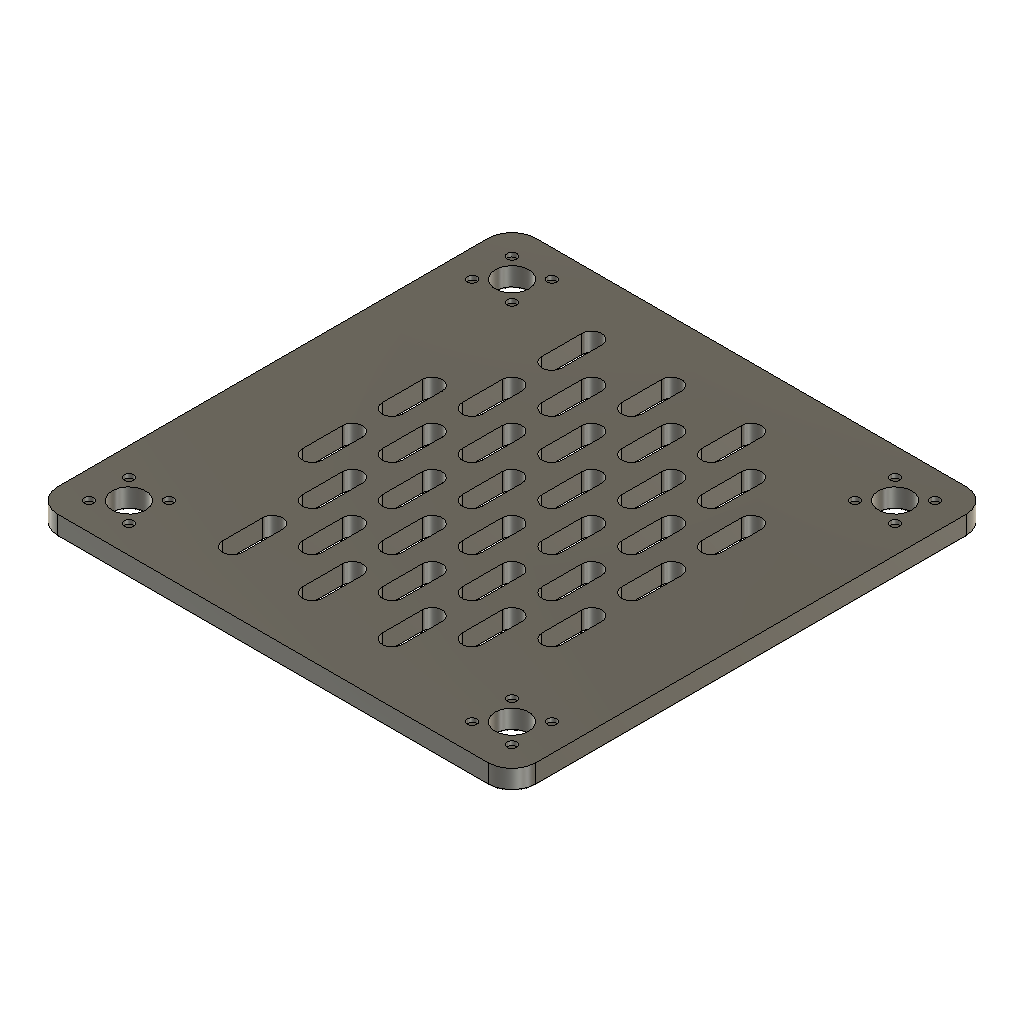
panel-standalone-v03 (Autodesk Fusion 360 design; units mm, degrees)
part number: 2026-10-27-17-32-38-234
part number: 2026-10-27-17-32-38-962
Autodesk Fusion 360 part; units mm, degrees
sketch "01 Panel blank sketch" plane through (0, 0, 0) normal (0, 0, 1) x (1, 0, 0) in component "Panel standalone"
  line L0 (0.1, 0.1) -> (119.9, 0.1)
  line L1 (119.9, 0.1) -> (119.9, 119.9)
  line L2 (119.9, 119.9) -> (0.1, 119.9)
  line L3 (0.1, 119.9) -> (0.1, 0.1)
  dimension "d57" = 0.1
  dimension "d58" = 0.1
  dimension "d59" = 119.8
  dimension "d60" = 119.8
  constraint horizontal L0
  constraint vertical L1
  constraint horizontal L2
  constraint vertical L3
  measures "d57" horizontal distance of origin L0.start
  measures "d58" vertical distance of origin L0.start
  measures "d59" horizontal distance of L0.start L0.end
  measures "d60" vertical distance of L0.end L1.end
extrude "01 Panel blank" add sketch "01 Panel blank sketch" along normal blind 5 in component "Panel standalone"
fillet "02 Rounded exterior corners" radius 6 4 edges at (0.1, 119.9, 2.5) (119.9, 119.9, 2.5) (119.9, 0.1, 2.5) (0.1, 0.1, 2.5) in component "Panel standalone"
sketch "03 A main constrained seed" plane through (0, 0, 0) normal (0, 0, 1) x (1, 0, 0) in component "Panel standalone"
  line L0 (47.5, 25) -> (47.5, 35)
  arc A0 (47.5, 35) -> (42.5, 35) centre (45, 35) ccw
  line L1 (42.5, 35) -> (42.5, 25)
  arc A1 (42.5, 25) -> (47.5, 25) centre (45, 25) ccw
  line L2 (45, 25) -> (45, 35) construction
  line L3 (45, 25) -> (55, 25) construction
  dimension "d65" = 5
  dimension "d66" = 10
  dimension "d67" = 90
  dimension "d68" = 10
  dimension "d69" = 45
  dimension "d70" = 25
  constraint tangent L0 A0
  constraint tangent A0 L1
  constraint tangent L1 A1
  constraint tangent L0 A1
  constraint parallel L0 L1
  constraint horizontal L3
  measures "d65" diameter of A0
  measures "d66" distance of A1.centre A0.centre
  measures "d67" angle of L2 L3
  measures "d68" horizontal distance of A1.centre L3.end
  measures "d69" horizontal distance of origin A1.centre
  measures "d70" vertical distance of origin A1.centre
extrude "03 A main through cut" cut sketch "03 A main constrained seed" along normal blind 5 in component "Panel standalone"
pattern_linear "03 A main lattice" count 3 spacing 20 along (1, 0, 0) count 4 spacing 20 along (0, 1, 0) of "03 A main through cut" in component "Panel standalone"
sketch "04 A end strip constrained seed" plane through (0, 0, 0) normal (0, 0, 1) x (1, 0, 0) in component "Panel standalone"
  line L0 (27.5, 45) -> (27.5, 55)
  arc A0 (27.5, 55) -> (22.5, 55) centre (25, 55) ccw
  line L1 (22.5, 55) -> (22.5, 45)
  arc A1 (22.5, 45) -> (27.5, 45) centre (25, 45) ccw
  line L2 (25, 45) -> (25, 55) construction
  line L3 (25, 45) -> (35, 45) construction
  dimension "d77" = 5
  dimension "d78" = 10
  dimension "d79" = 90
  dimension "d80" = 10
  dimension "d81" = 25
  dimension "d82" = 45
  constraint tangent L0 A0
  constraint tangent A0 L1
  constraint tangent L1 A1
  constraint tangent L0 A1
  constraint parallel L0 L1
  constraint horizontal L3
  measures "d77" diameter of A0
  measures "d78" distance of A1.centre A0.centre
  measures "d79" angle of L2 L3
  measures "d80" horizontal distance of A1.centre L3.end
  measures "d81" horizontal distance of origin A1.centre
  measures "d82" vertical distance of origin A1.centre
extrude "04 A end strip through cut" cut sketch "04 A end strip constrained seed" along normal blind 5 in component "Panel standalone"
pattern_linear "04 A end strip lattice" count 1 spacing 20 along (1, 0, 0) count 2 spacing 20 along (0, 1, 0) of "04 A end strip through cut" in component "Panel standalone"
sketch "05 B main constrained seed" plane through (0, 0, 0) normal (0, 0, 1) x (1, 0, 0) in component "Panel standalone"
  line L0 (37.5, 15) -> (37.5, 25)
  arc A0 (37.5, 25) -> (32.5, 25) centre (35, 25) ccw
  line L1 (32.5, 25) -> (32.5, 15)
  arc A1 (32.5, 15) -> (37.5, 15) centre (35, 15) ccw
  line L2 (35, 15) -> (35, 25) construction
  line L3 (35, 15) -> (45, 15) construction
  dimension "d89" = 5
  dimension "d90" = 10
  dimension "d91" = 90
  dimension "d92" = 10
  dimension "d93" = 35
  dimension "d94" = 15
  constraint tangent L0 A0
  constraint tangent A0 L1
  constraint tangent L1 A1
  constraint tangent L0 A1
  constraint parallel L0 L1
  constraint horizontal L3
  measures "d89" diameter of A0
  measures "d90" distance of A1.centre A0.centre
  measures "d91" angle of L2 L3
  measures "d92" horizontal distance of A1.centre L3.end
  measures "d93" horizontal distance of origin A1.centre
  measures "d94" vertical distance of origin A1.centre
extrude "05 B main through cut" cut sketch "05 B main constrained seed" along normal blind 5 in component "Panel standalone"
pattern_linear "05 B main lattice" count 3 spacing 20 along (1, 0, 0) count 5 spacing 20 along (0, 1, 0) of "05 B main through cut" in component "Panel standalone"
sketch "06 B end strip constrained seed" plane through (0, 0, 0) normal (0, 0, 1) x (1, 0, 0) in component "Panel standalone"
  line L0 (97.5, 35) -> (97.5, 45)
  arc A0 (97.5, 45) -> (92.5, 45) centre (95, 45) ccw
  line L1 (92.5, 45) -> (92.5, 35)
  arc A1 (92.5, 35) -> (97.5, 35) centre (95, 35) ccw
  line L2 (95, 35) -> (95, 45) construction
  line L3 (95, 35) -> (105, 35) construction
  dimension "d101" = 5
  dimension "d102" = 10
  dimension "d103" = 90
  dimension "d104" = 10
  dimension "d105" = 95
  dimension "d106" = 35
  constraint tangent L0 A0
  constraint tangent A0 L1
  constraint tangent L1 A1
  constraint tangent L0 A1
  constraint parallel L0 L1
  constraint horizontal L3
  measures "d101" diameter of A0
  measures "d102" distance of A1.centre A0.centre
  measures "d103" angle of L2 L3
  measures "d104" horizontal distance of A1.centre L3.end
  measures "d105" horizontal distance of origin A1.centre
  measures "d106" vertical distance of origin A1.centre
extrude "06 B end strip through cut" cut sketch "06 B end strip constrained seed" along normal blind 5 in component "Panel standalone"
pattern_linear "06 B end strip lattice" count 1 spacing 20 along (1, 0, 0) count 3 spacing 20 along (0, 1, 0) of "06 B end strip through cut" in component "Panel standalone"
sketch "07 Shared node clearance sketch" plane through (0, 0, 0) normal (0, 0, 1) x (1, 0, 0) in component "Panel standalone"
  circle A0 centre (12, 12) radius 4.2
  dimension "d113" = 12
  dimension "d114" = 12
  dimension "d115" = 8.4
  measures "d113" horizontal distance of origin A0.centre
  measures "d114" vertical distance of origin A0.centre
  measures "d115" diameter of A0
extrude "07 Shared node clearance" cut sketch "07 Shared node clearance sketch" along normal blind 5 in component "Panel standalone"
sketch "07 Shared node clearance sketch (1)" plane through (0, 0, 0) normal (0, 0, 1) x (1, 0, 0) in component "Panel standalone"
  circle A0 centre (12, 108) radius 4.2
  dimension "d118" = 12
  dimension "d119" = 108
  dimension "d120" = 8.4
  measures "d118" horizontal distance of origin A0.centre
  measures "d119" vertical distance of origin A0.centre
  measures "d120" diameter of A0
extrude "07 Shared node clearance (1)" cut sketch "07 Shared node clearance sketch (1)" along normal blind 5 in component "Panel standalone"
sketch "07 Shared node clearance sketch (2)" plane through (0, 0, 0) normal (0, 0, 1) x (1, 0, 0) in component "Panel standalone"
  circle A0 centre (108, 12) radius 4.2
  dimension "d123" = 108
  dimension "d124" = 12
  dimension "d125" = 8.4
  measures "d123" horizontal distance of origin A0.centre
  measures "d124" vertical distance of origin A0.centre
  measures "d125" diameter of A0
extrude "07 Shared node clearance (2)" cut sketch "07 Shared node clearance sketch (2)" along normal blind 5 in component "Panel standalone"
sketch "07 Shared node clearance sketch (3)" plane through (0, 0, 0) normal (0, 0, 1) x (1, 0, 0) in component "Panel standalone"
  circle A0 centre (108, 108) radius 4.2
  dimension "d128" = 108
  dimension "d129" = 108
  dimension "d130" = 8.4
  measures "d128" horizontal distance of origin A0.centre
  measures "d129" vertical distance of origin A0.centre
  measures "d130" diameter of A0
extrude "07 Shared node clearance (3)" cut sketch "07 Shared node clearance sketch (3)" along normal blind 5 in component "Panel standalone"
fillet "08 Rounded slot entrances and face edges" radius 0.4 2 faces at (112.4333, 61.6667, 0) (112.4333, 61.6667, 0) in component "Panel standalone"
ref_plane "WorkPlane1" through (0, 0, 5) normal (0, 0, 1) x (1, 0, 0) in component "Panel standalone"
sketch "10 Node register socket sketch" plane through (0, 0, 5) normal (0, 0, 1) x (1, 0, 0) in component "Panel standalone"
  circle A0 centre (7, 7) radius 1.2
  dimension "d137" = 7
  dimension "d138" = 7
  dimension "d139" = 2.4
  measures "d137" horizontal distance of origin A0.centre
  measures "d138" vertical distance of origin A0.centre
  measures "d139" diameter of A0
extrude "10 Node register socket" cut sketch "10 Node register socket sketch" against normal blind 1 in component "Panel standalone"
ref_plane "WorkPlane2" through (0, 0, 5) normal (0, 0, 1) x (1, 0, 0) in component "Panel standalone"
sketch "10 Node register socket sketch (1)" plane through (0, 0, 5) normal (0, 0, 1) x (1, 0, 0) in component "Panel standalone"
  circle A0 centre (7, 17) radius 1.2
  dimension "d144" = 7
  dimension "d145" = 17
  dimension "d146" = 2.4
  measures "d144" horizontal distance of origin A0.centre
  measures "d145" vertical distance of origin A0.centre
  measures "d146" diameter of A0
extrude "10 Node register socket (1)" cut sketch "10 Node register socket sketch (1)" against normal blind 1 in component "Panel standalone"
ref_plane "WorkPlane3" through (0, 0, 5) normal (0, 0, 1) x (1, 0, 0) in component "Panel standalone"
sketch "10 Node register socket sketch (2)" plane through (0, 0, 5) normal (0, 0, 1) x (1, 0, 0) in component "Panel standalone"
  circle A0 centre (17, 7) radius 1.2
  dimension "d151" = 17
  dimension "d152" = 7
  dimension "d153" = 2.4
  measures "d151" horizontal distance of origin A0.centre
  measures "d152" vertical distance of origin A0.centre
  measures "d153" diameter of A0
extrude "10 Node register socket (2)" cut sketch "10 Node register socket sketch (2)" against normal blind 1 in component "Panel standalone"
ref_plane "WorkPlane4" through (0, 0, 5) normal (0, 0, 1) x (1, 0, 0) in component "Panel standalone"
sketch "10 Node register socket sketch (3)" plane through (0, 0, 5) normal (0, 0, 1) x (1, 0, 0) in component "Panel standalone"
  circle A0 centre (17, 17) radius 1.2
  dimension "d158" = 17
  dimension "d159" = 17
  dimension "d160" = 2.4
  measures "d158" horizontal distance of origin A0.centre
  measures "d159" vertical distance of origin A0.centre
  measures "d160" diameter of A0
extrude "10 Node register socket (3)" cut sketch "10 Node register socket sketch (3)" against normal blind 1 in component "Panel standalone"
ref_plane "WorkPlane5" through (0, 0, 5) normal (0, 0, 1) x (1, 0, 0) in component "Panel standalone"
sketch "10 Node register socket sketch (4)" plane through (0, 0, 5) normal (0, 0, 1) x (1, 0, 0) in component "Panel standalone"
  circle A0 centre (7, 103) radius 1.2
  dimension "d165" = 7
  dimension "d166" = 103
  dimension "d167" = 2.4
  measures "d165" horizontal distance of origin A0.centre
  measures "d166" vertical distance of origin A0.centre
  measures "d167" diameter of A0
extrude "10 Node register socket (4)" cut sketch "10 Node register socket sketch (4)" against normal blind 1 in component "Panel standalone"
ref_plane "WorkPlane6" through (0, 0, 5) normal (0, 0, 1) x (1, 0, 0) in component "Panel standalone"
sketch "10 Node register socket sketch (5)" plane through (0, 0, 5) normal (0, 0, 1) x (1, 0, 0) in component "Panel standalone"
  circle A0 centre (7, 113) radius 1.2
  dimension "d172" = 7
  dimension "d173" = 113
  dimension "d174" = 2.4
  measures "d172" horizontal distance of origin A0.centre
  measures "d173" vertical distance of origin A0.centre
  measures "d174" diameter of A0
extrude "10 Node register socket (5)" cut sketch "10 Node register socket sketch (5)" against normal blind 1 in component "Panel standalone"
ref_plane "WorkPlane7" through (0, 0, 5) normal (0, 0, 1) x (1, 0, 0) in component "Panel standalone"
sketch "10 Node register socket sketch (6)" plane through (0, 0, 5) normal (0, 0, 1) x (1, 0, 0) in component "Panel standalone"
  circle A0 centre (17, 103) radius 1.2
  dimension "d179" = 17
  dimension "d180" = 103
  dimension "d181" = 2.4
  measures "d179" horizontal distance of origin A0.centre
  measures "d180" vertical distance of origin A0.centre
  measures "d181" diameter of A0
extrude "10 Node register socket (6)" cut sketch "10 Node register socket sketch (6)" against normal blind 1 in component "Panel standalone"
ref_plane "WorkPlane8" through (0, 0, 5) normal (0, 0, 1) x (1, 0, 0) in component "Panel standalone"
sketch "10 Node register socket sketch (7)" plane through (0, 0, 5) normal (0, 0, 1) x (1, 0, 0) in component "Panel standalone"
  circle A0 centre (17, 113) radius 1.2
  dimension "d186" = 17
  dimension "d187" = 113
  dimension "d188" = 2.4
  measures "d186" horizontal distance of origin A0.centre
  measures "d187" vertical distance of origin A0.centre
  measures "d188" diameter of A0
extrude "10 Node register socket (7)" cut sketch "10 Node register socket sketch (7)" against normal blind 1 in component "Panel standalone"
ref_plane "WorkPlane9" through (0, 0, 5) normal (0, 0, 1) x (1, 0, 0) in component "Panel standalone"
sketch "10 Node register socket sketch (8)" plane through (0, 0, 5) normal (0, 0, 1) x (1, 0, 0) in component "Panel standalone"
  circle A0 centre (103, 7) radius 1.2
  dimension "d193" = 103
  dimension "d194" = 7
  dimension "d195" = 2.4
  measures "d193" horizontal distance of origin A0.centre
  measures "d194" vertical distance of origin A0.centre
  measures "d195" diameter of A0
extrude "10 Node register socket (8)" cut sketch "10 Node register socket sketch (8)" against normal blind 1 in component "Panel standalone"
ref_plane "WorkPlane10" through (0, 0, 5) normal (0, 0, 1) x (1, 0, 0) in component "Panel standalone"
sketch "10 Node register socket sketch (9)" plane through (0, 0, 5) normal (0, 0, 1) x (1, 0, 0) in component "Panel standalone"
  circle A0 centre (103, 17) radius 1.2
  dimension "d200" = 103
  dimension "d201" = 17
  dimension "d202" = 2.4
  measures "d200" horizontal distance of origin A0.centre
  measures "d201" vertical distance of origin A0.centre
  measures "d202" diameter of A0
extrude "10 Node register socket (9)" cut sketch "10 Node register socket sketch (9)" against normal blind 1 in component "Panel standalone"
ref_plane "WorkPlane11" through (0, 0, 5) normal (0, 0, 1) x (1, 0, 0) in component "Panel standalone"
sketch "10 Node register socket sketch (10)" plane through (0, 0, 5) normal (0, 0, 1) x (1, 0, 0) in component "Panel standalone"
  circle A0 centre (113, 7) radius 1.2
  dimension "d207" = 113
  dimension "d208" = 7
  dimension "d209" = 2.4
  measures "d207" horizontal distance of origin A0.centre
  measures "d208" vertical distance of origin A0.centre
  measures "d209" diameter of A0
extrude "10 Node register socket (10)" cut sketch "10 Node register socket sketch (10)" against normal blind 1 in component "Panel standalone"
ref_plane "WorkPlane12" through (0, 0, 5) normal (0, 0, 1) x (1, 0, 0) in component "Panel standalone"
sketch "10 Node register socket sketch (11)" plane through (0, 0, 5) normal (0, 0, 1) x (1, 0, 0) in component "Panel standalone"
  circle A0 centre (113, 17) radius 1.2
  dimension "d214" = 113
  dimension "d215" = 17
  dimension "d216" = 2.4
  measures "d214" horizontal distance of origin A0.centre
  measures "d215" vertical distance of origin A0.centre
  measures "d216" diameter of A0
extrude "10 Node register socket (11)" cut sketch "10 Node register socket sketch (11)" against normal blind 1 in component "Panel standalone"
ref_plane "WorkPlane13" through (0, 0, 5) normal (0, 0, 1) x (1, 0, 0) in component "Panel standalone"
sketch "10 Node register socket sketch (12)" plane through (0, 0, 5) normal (0, 0, 1) x (1, 0, 0) in component "Panel standalone"
  circle A0 centre (103, 103) radius 1.2
  dimension "d221" = 103
  dimension "d222" = 103
  dimension "d223" = 2.4
  measures "d221" horizontal distance of origin A0.centre
  measures "d222" vertical distance of origin A0.centre
  measures "d223" diameter of A0
extrude "10 Node register socket (12)" cut sketch "10 Node register socket sketch (12)" against normal blind 1 in component "Panel standalone"
ref_plane "WorkPlane14" through (0, 0, 5) normal (0, 0, 1) x (1, 0, 0) in component "Panel standalone"
sketch "10 Node register socket sketch (13)" plane through (0, 0, 5) normal (0, 0, 1) x (1, 0, 0) in component "Panel standalone"
  circle A0 centre (103, 113) radius 1.2
  dimension "d228" = 103
  dimension "d229" = 113
  dimension "d230" = 2.4
  measures "d228" horizontal distance of origin A0.centre
  measures "d229" vertical distance of origin A0.centre
  measures "d230" diameter of A0
extrude "10 Node register socket (13)" cut sketch "10 Node register socket sketch (13)" against normal blind 1 in component "Panel standalone"
ref_plane "WorkPlane15" through (0, 0, 5) normal (0, 0, 1) x (1, 0, 0) in component "Panel standalone"
sketch "10 Node register socket sketch (14)" plane through (0, 0, 5) normal (0, 0, 1) x (1, 0, 0) in component "Panel standalone"
  circle A0 centre (113, 103) radius 1.2
  dimension "d235" = 113
  dimension "d236" = 103
  dimension "d237" = 2.4
  measures "d235" horizontal distance of origin A0.centre
  measures "d236" vertical distance of origin A0.centre
  measures "d237" diameter of A0
extrude "10 Node register socket (14)" cut sketch "10 Node register socket sketch (14)" against normal blind 1 in component "Panel standalone"
ref_plane "WorkPlane16" through (0, 0, 5) normal (0, 0, 1) x (1, 0, 0) in component "Panel standalone"
sketch "10 Node register socket sketch (15)" plane through (0, 0, 5) normal (0, 0, 1) x (1, 0, 0) in component "Panel standalone"
  circle A0 centre (113, 113) radius 1.2
  dimension "d242" = 113
  dimension "d243" = 113
  dimension "d244" = 2.4
  measures "d242" horizontal distance of origin A0.centre
  measures "d243" vertical distance of origin A0.centre
  measures "d244" diameter of A0
extrude "10 Node register socket (15)" cut sketch "10 Node register socket sketch (15)" against normal blind 1 in component "Panel standalone"
component "Panel standalone" placed x (1, 0, 0) y (0, 1, 0) z (0, 0, 1) at (0, 0, 0)
equation "columns = 6" comment "Even integer 4..14; each cell is 20 mm"
equation "rows = 6" comment "Even integer 4..14"
equation "pitch = 20 mm" comment "Keep for dense SKADIS compatible lattice"
equation "panelWidth = columns * pitch" comment "Nominal module pitch X"
equation "panelHeight = rows * pitch" comment "Nominal module pitch Y"
equation "seamGap = 0.2 mm" comment "Physical envelope shrinks around fixed lattice"
equation "boardThickness = 5 mm" comment "Fit-test with real hooks"
equation "slotWidth = 5 mm" comment "Minimum throat width"
equation "slotHeight = 15 mm" comment "Minimum throat height"
equation "entryRadius = 0.4 mm" comment "Front slot and perimeter edge rounding"
equation "cornerRadius = 6 mm" comment "Plan-view panel corner rounding"
equation "hookClearance = 10 mm" comment "PROVISIONAL: board rear to front of extrusion"
equation "frameZ = boardThickness + hookClearance" comment "Front extrusion datum"
equation "mountInset = 12 mm" comment "Exterior node inset from outside module edge"
equation "mountBore = 8.4 mm" comment "Clearance around 8 mm metal shoulder"
equation "capDiameter = 18 mm" comment "Visible decorative mounting disk"
equation "capThickness = 5 mm" comment "Metal clamping cap / washer"
equation "seatThickness = 2 mm" comment "Printed rear bearing washer"
equation "screwDiameter = 5 mm" comment "Nominal M5 reference, threads omitted"
equation "screwClearance = 5.5 mm" comment "Cap and spacer bore"
equation "keyWidth = 4 mm" comment "Registration key corridor width"
equation "keyThickness = 2 mm" comment "Rear removable key body"
equation "keyPegDiameter = 3 mm" comment "Rear locating peg"
equation "keySocketDiameter = 3.4 mm" comment "0.2 mm radial starting fit"
equation "keyPegHeight = 0.8 mm" comment "Peg penetration"
equation "keySocketDepth = 1 mm" comment "Blind locating pocket"
equation "profileMouth = 6.28 mm" comment "User measured mouth"
equation "profileCavity = 11 mm" comment "User measured widest cavity"
equation "profileDepth = 6.2 mm" comment "User measured face-to-floor depth"
equation "profileFloor = 5.7 mm" comment "User estimate, lower confidence"
equation "profileLip = 1.5 mm" comment "Unmeasured; tentative comparable catalog value"
equation "profileTaperStart = profileDepth - ( profileCavity - profileFloor ) / 2" comment "Assumed 45-degree inner slopes"
equation "profileBore = 5 mm" comment "Unmeasured central bore, reference only"
equation "nutWidth = 8.8 mm" comment "Provisional low-profile METAL T-nut envelope, not old rectangular carrier"
equation "nutLength = 12 mm" comment "End-loaded anti-rotation metal nut envelope"
equation "nutThickness = 2.7 mm" comment "Thin nut reference; fit/load still unverified"
equation "jointLeg = 18 mm" comment "In-bay angle footprint"
equation "jointThickness = 3 mm" comment "Metal bracket thickness"
equation "jointDepth = 16 mm" comment "Bracket depth within 20 mm rail"
equation "sideScrewLength = 8 mm" comment "M5x8 reference; check against actual bracket and nut"
equation "registerPin = 2 mm" comment "Node-seat locating pins"
equation "registerSocket = 2.4 mm" comment "Starting printed locating clearance"
equation "registerPinHeight = 0.8 mm" comment "Pin into rear socket"
equation "registerSocketDepth = 1 mm" comment "Blind panel socket"
equation "registerOffset = 5 mm" comment "Four pegs at node +/- offset"
equation "wallTabHeight = 24 mm" comment "Tab along extrusion"
equation "wallTabReach = 22 mm" comment "Tab into open bay"
equation "wallAnchorClearance = 6.5 mm" comment "Placeholder wall anchor interface"
equation "wallShim = 0 mm" comment "Only actual leveling shims; no designed rear air gap"
equation "wallDriverDiameter = 12 mm" comment "Clear tool envelope in open bays"
equation "keyDriverDiameter = 5 mm" comment "Short hex-key working-leg envelope"
equation "keyDriverReach = 20 mm" comment "Short hex-key working-leg reach"
equation "panelLeft = 1" comment "0 internal / 1 finished; full cell border and inset mounting"
equation "panelRight = 1" comment "0 internal / 1 finished; full cell border and inset mounting"
equation "panelBottom = 1" comment "0 internal / 1 finished; full cell border and inset mounting"
equation "panelTop = 1" comment "0 internal / 1 finished; full cell border and inset mounting"
equation "d57 = abs(( 0 mm ) + seamGap / 2)"
equation "d58 = abs(( 0 mm ) + seamGap / 2)"
equation "d59 = panelWidth - seamGap"
equation "d60 = panelHeight - seamGap"
equation "d61 = boardThickness"
equation "d64 = cornerRadius"
equation "d65 = slotWidth"
equation "d66 = slotHeight - slotWidth"
equation "d68 = pitch / 2"
equation "d69 = abs(( 0 mm ) + pitch / 4 + pitch * ( panelLeft + 1 ))"
equation "d70 = abs(( ( 0 mm ) + pitch / 2 + pitch * panelBottom ) - ( slotHeight - slotWidth ) / 2)"
equation "d71 = boardThickness"
equation "d73 = columns - panelLeft - panelRight - 1"
equation "d74 = rows - panelBottom - panelTop"
equation "d75 = pitch"
equation "d76 = pitch"
equation "d77 = slotWidth"
equation "d78 = slotHeight - slotWidth"
equation "d80 = pitch / 2"
equation "d81 = abs(( 0 mm ) + pitch / 4 + pitch * panelLeft)"
equation "d82 = abs(( ( 0 mm ) + 3 * pitch / 2 + pitch * panelBottom ) - ( slotHeight - slotWidth ) / 2)"
equation "d83 = boardThickness"
equation "d86 = rows - panelBottom - panelTop - 2"
equation "d87 = pitch"
equation "d88 = pitch"
equation "d89 = slotWidth"
equation "d90 = slotHeight - slotWidth"
equation "d92 = pitch / 2"
equation "d93 = abs(( 0 mm ) + 3 * pitch / 4 + pitch * panelLeft)"
equation "d94 = abs(( ( 0 mm ) + pitch * panelBottom ) - ( slotHeight - slotWidth ) / 2)"
equation "d95 = boardThickness"
equation "d97 = columns - panelLeft - panelRight - 1"
equation "d98 = rows + 1 - panelBottom - panelTop"
equation "d99 = pitch"
equation "d100 = pitch"
equation "d101 = slotWidth"
equation "d102 = slotHeight - slotWidth"
equation "d104 = pitch / 2"
equation "d105 = abs(( 0 mm ) + panelWidth - pitch / 4 - pitch * panelRight)"
equation "d106 = abs(( ( 0 mm ) + pitch + pitch * panelBottom ) - ( slotHeight - slotWidth ) / 2)"
equation "d107 = boardThickness"
equation "d110 = rows - 1 - panelBottom - panelTop"
equation "d111 = pitch"
equation "d112 = pitch"
equation "d113 = abs(( 0 mm ) + mountInset * panelLeft)"
equation "d114 = abs(( 0 mm ) + mountInset * panelBottom)"
equation "d115 = mountBore"
equation "d116 = boardThickness"
equation "d118 = abs(( 0 mm ) + mountInset * panelLeft)"
equation "d119 = abs(( 0 mm ) + panelHeight - mountInset * panelTop)"
equation "d120 = mountBore"
equation "d121 = boardThickness"
equation "d123 = abs(( 0 mm ) + panelWidth - mountInset * panelRight)"
equation "d124 = abs(( 0 mm ) + mountInset * panelBottom)"
equation "d125 = mountBore"
equation "d126 = boardThickness"
equation "d128 = abs(( 0 mm ) + panelWidth - mountInset * panelRight)"
equation "d129 = abs(( 0 mm ) + panelHeight - mountInset * panelTop)"
equation "d130 = mountBore"
equation "d131 = boardThickness"
equation "d134 = entryRadius"
equation "d135 = boardThickness"
equation "d137 = abs(( 0 mm ) + mountInset * panelLeft + ( -1 ) * registerOffset)"
equation "d138 = abs(( 0 mm ) + mountInset * panelBottom + ( -1 ) * registerOffset)"
equation "d139 = registerSocket"
equation "d140 = -registerSocketDepth"
equation "d142 = boardThickness"
equation "d144 = abs(( 0 mm ) + mountInset * panelLeft + ( -1 ) * registerOffset)"
equation "d145 = abs(( 0 mm ) + mountInset * panelBottom + ( 1 ) * registerOffset)"
equation "d146 = registerSocket"
equation "d147 = -registerSocketDepth"
equation "d149 = boardThickness"
equation "d151 = abs(( 0 mm ) + mountInset * panelLeft + ( 1 ) * registerOffset)"
equation "d152 = abs(( 0 mm ) + mountInset * panelBottom + ( -1 ) * registerOffset)"
equation "d153 = registerSocket"
equation "d154 = -registerSocketDepth"
equation "d156 = boardThickness"
equation "d158 = abs(( 0 mm ) + mountInset * panelLeft + ( 1 ) * registerOffset)"
equation "d159 = abs(( 0 mm ) + mountInset * panelBottom + ( 1 ) * registerOffset)"
equation "d160 = registerSocket"
equation "d161 = -registerSocketDepth"
equation "d163 = boardThickness"
equation "d165 = abs(( 0 mm ) + mountInset * panelLeft + ( -1 ) * registerOffset)"
equation "d166 = abs(( 0 mm ) + panelHeight - mountInset * panelTop + ( -1 ) * registerOffset)"
equation "d167 = registerSocket"
equation "d168 = -registerSocketDepth"
equation "d170 = boardThickness"
equation "d172 = abs(( 0 mm ) + mountInset * panelLeft + ( -1 ) * registerOffset)"
equation "d173 = abs(( 0 mm ) + panelHeight - mountInset * panelTop + ( 1 ) * registerOffset)"
equation "d174 = registerSocket"
equation "d175 = -registerSocketDepth"
equation "d177 = boardThickness"
equation "d179 = abs(( 0 mm ) + mountInset * panelLeft + ( 1 ) * registerOffset)"
equation "d180 = abs(( 0 mm ) + panelHeight - mountInset * panelTop + ( -1 ) * registerOffset)"
equation "d181 = registerSocket"
equation "d182 = -registerSocketDepth"
equation "d184 = boardThickness"
equation "d186 = abs(( 0 mm ) + mountInset * panelLeft + ( 1 ) * registerOffset)"
equation "d187 = abs(( 0 mm ) + panelHeight - mountInset * panelTop + ( 1 ) * registerOffset)"
equation "d188 = registerSocket"
equation "d189 = -registerSocketDepth"
equation "d191 = boardThickness"
equation "d193 = abs(( 0 mm ) + panelWidth - mountInset * panelRight + ( -1 ) * registerOffset)"
equation "d194 = abs(( 0 mm ) + mountInset * panelBottom + ( -1 ) * registerOffset)"
equation "d195 = registerSocket"
equation "d196 = -registerSocketDepth"
equation "d198 = boardThickness"
equation "d200 = abs(( 0 mm ) + panelWidth - mountInset * panelRight + ( -1 ) * registerOffset)"
equation "d201 = abs(( 0 mm ) + mountInset * panelBottom + ( 1 ) * registerOffset)"
equation "d202 = registerSocket"
equation "d203 = -registerSocketDepth"
equation "d205 = boardThickness"
equation "d207 = abs(( 0 mm ) + panelWidth - mountInset * panelRight + ( 1 ) * registerOffset)"
equation "d208 = abs(( 0 mm ) + mountInset * panelBottom + ( -1 ) * registerOffset)"
equation "d209 = registerSocket"
equation "d210 = -registerSocketDepth"
equation "d212 = boardThickness"
equation "d214 = abs(( 0 mm ) + panelWidth - mountInset * panelRight + ( 1 ) * registerOffset)"
equation "d215 = abs(( 0 mm ) + mountInset * panelBottom + ( 1 ) * registerOffset)"
equation "d216 = registerSocket"
equation "d217 = -registerSocketDepth"
equation "d219 = boardThickness"
equation "d221 = abs(( 0 mm ) + panelWidth - mountInset * panelRight + ( -1 ) * registerOffset)"
equation "d222 = abs(( 0 mm ) + panelHeight - mountInset * panelTop + ( -1 ) * registerOffset)"
equation "d223 = registerSocket"
equation "d224 = -registerSocketDepth"
equation "d226 = boardThickness"
equation "d228 = abs(( 0 mm ) + panelWidth - mountInset * panelRight + ( -1 ) * registerOffset)"
equation "d229 = abs(( 0 mm ) + panelHeight - mountInset * panelTop + ( 1 ) * registerOffset)"
equation "d230 = registerSocket"
equation "d231 = -registerSocketDepth"
equation "d233 = boardThickness"
equation "d235 = abs(( 0 mm ) + panelWidth - mountInset * panelRight + ( 1 ) * registerOffset)"
equation "d236 = abs(( 0 mm ) + panelHeight - mountInset * panelTop + ( -1 ) * registerOffset)"
equation "d237 = registerSocket"
equation "d238 = -registerSocketDepth"
equation "d240 = boardThickness"
equation "d242 = abs(( 0 mm ) + panelWidth - mountInset * panelRight + ( 1 ) * registerOffset)"
equation "d243 = abs(( 0 mm ) + panelHeight - mountInset * panelTop + ( 1 ) * registerOffset)"
equation "d244 = registerSocket"
equation "d245 = -registerSocketDepth"
named bodies: "Panel standalone"
